Autodesk Fusion 360 part; units mm, degrees
(part 11 of 28)
  line L2789 (27.591, 54.8062) -> (27.7738, 54.7468)
  line L2790 (27.7738, 54.7468) -> (27.9451, 54.6595)
  line L2791 (27.9451, 54.6595) -> (28.1006, 54.5465)
  line L2792 (28.1006, 54.5465) -> (28.2365, 54.4106)
  line L2793 (28.2365, 54.4106) -> (28.3495, 54.2551)
  line L2794 (28.3495, 54.2551) -> (28.3869, 54.1816)
  line L2795 (28.3869, 54.1816) -> (32.118, 57.9127)
  line L2796 (32.118, 57.9127) -> (32.118, 59.7489)
  line L2797 (32.118, 59.7489) -> (32.0649, 59.7759)
  line L2798 (32.0649, 59.7759) -> (31.9062, 59.8912)
  line L2799 (31.9062, 59.8912) -> (31.7675, 60.0299)
  line L2800 (31.7675, 60.0299) -> (31.6522, 60.1886)
  line L2801 (31.6522, 60.1886) -> (31.5632, 60.3634)
  line L2802 (31.5632, 60.3634) -> (31.5026, 60.5499)
  line L2803 (31.5026, 60.5499) -> (31.4719, 60.7437)
  line L2804 (31.4719, 60.7437) -> (31.468, 60.8417)
  line L2805 (31.468, 60.8417) -> (31.468, 61.3417)
  line L2806 (31.468, 61.3417) -> (31.4719, 61.4398)
  line L2807 (31.4719, 61.4398) -> (31.4787, 61.4826)
  line L2808 (31.4787, 61.4826) -> (26.2873, 66.6739)
  line L2809 (26.2873, 66.6739) -> (26.2356, 66.7329)
  line L2810 (26.2356, 66.7329) -> (26.1573, 66.8686)
  line L2811 (26.1573, 66.8686) -> (26.1167, 67.0199)
  line L2812 (26.1167, 67.0199) -> (26.1116, 67.0982)
  line L2813 (26.1116, 67.0982) -> (26.1116, 73.4443)
  line L2814 (26.1116, 73.4443) -> (26.0772, 73.4673)
  line L2815 (26.0772, 73.4673) -> (25.9386, 73.6059)
  line L2816 (25.9386, 73.6059) -> (25.8297, 73.7689)
  line L2817 (25.8297, 73.7689) -> (25.7547, 73.95)
  line L2818 (25.7547, 73.95) -> (25.7164, 74.1423)
  line L2819 (25.7164, 74.1423) -> (25.7116, 74.2403)
  line L2820 (25.7116, 74.2403) -> (25.7116, 75.4403)
  line L2821 (25.7116, 75.4403) -> (25.7164, 75.5383)
  line L2822 (25.7164, 75.5383) -> (25.7547, 75.7306)
  line L2823 (25.7547, 75.7306) -> (25.8297, 75.9117)
  line L2824 (25.8297, 75.9117) -> (25.9386, 76.0747)
  line L2825 (25.9386, 76.0747) -> (26.0772, 76.2133)
  line L2826 (26.0772, 76.2133) -> (26.2402, 76.3222)
  line L2827 (26.2402, 76.3222) -> (26.4213, 76.3972)
  line L2828 (26.4213, 76.3972) -> (26.6136, 76.4355)
  line L2829 (26.6136, 76.4355) -> (26.8096, 76.4355)
  line L2830 (26.8096, 76.4355) -> (27.0019, 76.3972)
  line L2831 (61.9269, 76.3972) -> (62.108, 76.3222)
  line L2832 (62.108, 76.3222) -> (62.271, 76.2133)
  line L2833 (62.271, 76.2133) -> (62.4096, 76.0747)
  line L2834 (62.4096, 76.0747) -> (62.5185, 75.9117)
  line L2835 (62.5185, 75.9117) -> (62.5935, 75.7306)
  line L2836 (62.5935, 75.7306) -> (62.6318, 75.5383)
  line L2837 (62.6318, 75.5383) -> (62.6366, 75.4403)
  line L2838 (62.6366, 75.4403) -> (62.6366, 74.2403)
  line L2839 (62.6366, 74.2403) -> (62.6318, 74.1423)
  line L2840 (62.6318, 74.1423) -> (62.5935, 73.95)
  line L2841 (62.5935, 73.95) -> (62.5185, 73.7689)
  line L2842 (62.5185, 73.7689) -> (62.4096, 73.6059)
  line L2843 (62.4096, 73.6059) -> (62.271, 73.4673)
  line L2844 (62.271, 73.4673) -> (62.2366, 73.4443)
  line L2845 (62.2366, 73.4443) -> (62.2366, 67.3467)
  line L2846 (62.2366, 67.3467) -> (67.113, 62.4703)
  line L2847 (67.113, 62.4703) -> (67.1647, 62.4966)
  line L2848 (67.1647, 62.4966) -> (67.3512, 62.5572)
  line L2849 (67.3512, 62.5572) -> (67.545, 62.5879)
  line L2850 (67.545, 62.5879) -> (67.7411, 62.5879)
  line L2851 (67.7411, 62.5879) -> (67.9348, 62.5572)
  line L2852 (67.9349, 62.5572) -> (68.1214, 62.4966)
  line L2853 (68.1214, 62.4966) -> (68.2962, 62.4075)
  line L2854 (68.2962, 62.4075) -> (68.4549, 62.2922)
  line L2855 (68.4549, 62.2922) -> (68.5935, 62.1536)
  line L2856 (68.5935, 62.1536) -> (68.7088, 61.9949)
  line L2857 (68.7088, 61.9949) -> (68.7979, 61.8201)
  line L2858 (68.7979, 61.8201) -> (68.8585, 61.6335)
  line L2859 (68.8585, 61.6335) -> (68.8892, 61.4398)
  line L2860 (68.8892, 61.4398) -> (68.893, 61.3417)
  line L2861 (68.893, 61.3417) -> (68.893, 60.8417)
  line L2862 (68.893, 60.8417) -> (68.8892, 60.7437)
  line L2863 (68.8892, 60.7437) -> (68.8585, 60.5499)
  line L2864 (68.8585, 60.5499) -> (68.7979, 60.3634)
  line L2865 (68.7979, 60.3634) -> (68.7088, 60.1886)
  line L2866 (68.7088, 60.1886) -> (68.5935, 60.0299)
  line L2867 (68.5935, 60.0299) -> (68.4549, 59.8912)
  line L2868 (68.4549, 59.8912) -> (68.2962, 59.7759)
  line L2869 (68.2962, 59.7759) -> (68.243, 59.7489)
  line L2870 (68.243, 59.7489) -> (68.243, 57.9582)
  line L2871 (68.243, 57.9582) -> (68.2499, 57.9463)
  line L2872 (68.2499, 57.9463) -> (68.2904, 57.795)
  line L2873 (68.2904, 57.795) -> (68.2904, 57.6384)
  line L2874 (68.2904, 57.6384) -> (68.2499, 57.4871)
  line L2875 (68.2499, 57.4871) -> (68.1716, 57.3515)
  line L2876 (68.1716, 57.3515) -> (68.1716, 57.3515)
  line L2877 (68.1716, 57.3515) -> (68.1198, 57.2925)
  line L2878 (68.1198, 57.2925) -> (63.7431, 52.9157)
  line L2879 (63.7431, 52.9157) -> (63.6841, 52.864)
  line L2880 (63.6841, 52.864) -> (63.5485, 52.7857)
  line L2881 (63.5485, 52.7857) -> (63.4114, 52.7489)
  line L2882 (63.4114, 52.7489) -> (63.3618, 52.5962)
  line L2883 (63.3618, 52.5962) -> (63.2745, 52.4249)
  line L2884 (63.2745, 52.4249) -> (63.1615, 52.2694)
  line L2885 (63.1615, 52.2694) -> (63.0256, 52.1335)
  line L2886 (63.0256, 52.1335) -> (62.8701, 52.0205)
  line L2887 (62.8701, 52.0205) -> (62.6988, 51.9332)
  line L2888 (62.6988, 51.9332) -> (62.516, 51.8738)
  line L2889 (62.516, 51.8738) -> (62.3261, 51.8438)
  line L2890 (62.3261, 51.8438) -> (62.1339, 51.8438)
  line L2891 (62.1339, 51.8438) -> (61.944, 51.8738)
  line L2892 (61.944, 51.8738) -> (61.7612, 51.9332)
  line L2893 (61.7612, 51.9332) -> (61.5899, 52.0205)
  line L2894 (61.5899, 52.0205) -> (61.4344, 52.1335)
  line L2895 (61.4344, 52.1335) -> (61.2985, 52.2694)
  line L2896 (61.2985, 52.2694) -> (61.1855, 52.4249)
  line L2897 (61.1855, 52.4249) -> (61.0982, 52.5962)
  line L2898 (61.0982, 52.5962) -> (61.0388, 52.779)
  line L2899 (61.0388, 52.779) -> (61.0088, 52.9689)
  line L2900 (61.0088, 52.9689) -> (61.005, 53.065)
  line L2901 (61.005, 53.065) -> (61.005, 53.615)
  line L2902 (61.005, 53.615) -> (61.0088, 53.7111)
  line L2903 (61.0088, 53.7111) -> (61.0388, 53.901)
  line L2904 (61.0388, 53.901) -> (61.0982, 54.0838)
  line L2905 (61.0982, 54.0838) -> (61.1855, 54.2551)
  line L2906 (61.1855, 54.2551) -> (61.2985, 54.4106)
  line L2907 (61.2985, 54.4106) -> (61.4344, 54.5465)
  line L2908 (61.4344, 54.5465) -> (61.5899, 54.6595)
  line L2909 (61.5899, 54.6595) -> (61.7612, 54.7468)
  line L2910 (61.7612, 54.7468) -> (61.944, 54.8062)
  line L2911 (61.944, 54.8062) -> (62.1339, 54.8362)
  line L2912 (62.1339, 54.8362) -> (62.3261, 54.8362)
  line L2913 (62.3261, 54.8362) -> (62.516, 54.8062)
  line L2914 (62.516, 54.8062) -> (62.6988, 54.7468)
  line L2915 (62.6988, 54.7468) -> (62.8701, 54.6595)
  line L2916 (62.8701, 54.6595) -> (63.0256, 54.5465)
  line L2917 (63.0256, 54.5465) -> (63.1615, 54.4106)
  line L2918 (63.1615, 54.4106) -> (63.2745, 54.2551)
  line L2919 (63.2745, 54.2551) -> (63.3119, 54.1816)
  line L2920 (63.3119, 54.1816) -> (67.043, 57.9127)
  line L2921 (67.043, 57.9127) -> (67.043, 59.7489)
  line L2922 (67.043, 59.7489) -> (66.9899, 59.7759)
  line L2923 (66.9899, 59.7759) -> (66.8312, 59.8912)
  line L2924 (66.8312, 59.8912) -> (66.6925, 60.0299)
  line L2925 (66.6925, 60.0299) -> (66.5772, 60.1886)
  line L2926 (66.5772, 60.1886) -> (66.4882, 60.3634)
  line L2927 (66.4882, 60.3634) -> (66.4276, 60.5499)
  line L2928 (66.4276, 60.5499) -> (66.3969, 60.7437)
  line L2929 (66.3969, 60.7437) -> (66.393, 60.8417)
  line L2930 (66.393, 60.8417) -> (66.393, 61.3417)
  line L2931 (66.393, 61.3417) -> (66.3969, 61.4398)
  line L2932 (66.3969, 61.4398) -> (66.4037, 61.4826)
  line L2933 (66.4037, 61.4826) -> (61.2123, 66.6739)
  line L2934 (61.2123, 66.6739) -> (61.1606, 66.7329)
  line L2935 (61.1606, 66.7329) -> (61.0823, 66.8686)
  line L2936 (61.0823, 66.8686) -> (61.0417, 67.0199)
  line L2937 (61.0417, 67.0199) -> (61.0366, 67.0982)
  line L2938 (61.0366, 67.0982) -> (61.0366, 73.4443)
  line L2939 (61.0366, 73.4443) -> (61.0022, 73.4673)
  line L2940 (61.0022, 73.4673) -> (60.8636, 73.6059)
  line L2941 (60.8636, 73.6059) -> (60.7547, 73.7689)
  line L2942 (60.7547, 73.7689) -> (60.6797, 73.95)
  line L2943 (60.6797, 73.95) -> (60.6414, 74.1423)
  line L2944 (60.6414, 74.1423) -> (60.6366, 74.2403)
  line L2945 (60.6366, 74.2403) -> (60.6366, 75.4403)
  line L2946 (60.6366, 75.4403) -> (60.6414, 75.5383)
  line L2947 (60.6414, 75.5383) -> (60.6797, 75.7306)
  line L2948 (60.6797, 75.7306) -> (60.7547, 75.9117)
  line L2949 (60.7547, 75.9117) -> (60.8636, 76.0747)
  line L2950 (60.8636, 76.0747) -> (61.0022, 76.2133)
  line L2951 (61.0022, 76.2133) -> (61.1652, 76.3222)
  line L2952 (61.1652, 76.3222) -> (61.3463, 76.3972)
  line L2953 (61.3463, 76.3972) -> (61.5386, 76.4355)
  line L2954 (61.5386, 76.4355) -> (61.7346, 76.4355)
  line L2955 (61.7346, 76.4355) -> (61.9269, 76.3972)
  line L2956 (96.8519, 76.3972) -> (97.033, 76.3222)
  line L2957 (97.033, 76.3222) -> (97.196, 76.2133)
  line L2958 (97.196, 76.2133) -> (97.3346, 76.0747)
  line L2959 (97.3346, 76.0747) -> (97.4435, 75.9117)
  line L2960 (97.4435, 75.9117) -> (97.5185, 75.7306)
  line L2961 (97.5185, 75.7306) -> (97.5568, 75.5383)
  line L2962 (97.5568, 75.5383) -> (97.5616, 75.4403)
  line L2963 (97.5616, 75.4403) -> (97.5616, 74.2403)
  line L2964 (97.5616, 74.2403) -> (97.5568, 74.1423)
  line L2965 (97.5568, 74.1423) -> (97.5185, 73.95)
  line L2966 (97.5185, 73.95) -> (97.4435, 73.7689)
  line L2967 (97.4435, 73.7689) -> (97.3346, 73.6059)
  line L2968 (97.3346, 73.6059) -> (97.196, 73.4673)
  line L2969 (97.196, 73.4673) -> (97.1616, 73.4443)
  line L2970 (97.1616, 73.4443) -> (97.1616, 67.3467)
  line L2971 (97.1616, 67.3467) -> (102.038, 62.4703)
  line L2972 (102.038, 62.4703) -> (102.0897, 62.4966)
  line L2973 (102.0897, 62.4966) -> (102.2762, 62.5572)
  line L2974 (102.2762, 62.5572) -> (102.47, 62.5879)
  line L2975 (102.47, 62.5879) -> (102.6661, 62.5879)
  line L2976 (102.6661, 62.5879) -> (102.8598, 62.5572)
  line L2977 (102.8598, 62.5572) -> (103.0464, 62.4966)
  line L2978 (103.0464, 62.4966) -> (103.2212, 62.4075)
  line L2979 (103.2212, 62.4075) -> (103.3799, 62.2922)
  line L2980 (103.3799, 62.2922) -> (103.5186, 62.1536)
  line L2981 (103.5186, 62.1536) -> (103.6338, 61.9949)
  line L2982 (103.6338, 61.9949) -> (103.7229, 61.8201)
  line L2983 (103.7229, 61.8201) -> (103.7835, 61.6335)
  line L2984 (103.7835, 61.6335) -> (103.8142, 61.4398)
  line L2985 (103.8142, 61.4398) -> (103.818, 61.3417)
  line L2986 (103.818, 61.3417) -> (103.818, 60.8417)
  line L2987 (103.818, 60.8417) -> (103.8142, 60.7437)
  line L2988 (103.8142, 60.7437) -> (103.7835, 60.5499)
  line L2989 (103.7835, 60.5499) -> (103.7229, 60.3634)
  line L2990 (103.7229, 60.3634) -> (103.6338, 60.1886)
  line L2991 (103.6338, 60.1886) -> (103.5186, 60.0299)
  line L2992 (103.5186, 60.0299) -> (103.3799, 59.8912)
  line L2993 (103.3799, 59.8912) -> (103.2212, 59.7759)
  line L2994 (103.2212, 59.7759) -> (103.168, 59.7489)
  line L2995 (103.168, 59.7489) -> (103.168, 57.9582)
  line L2996 (103.168, 57.9582) -> (103.1749, 57.9463)
  line L2997 (103.1749, 57.9463) -> (103.2154, 57.795)
  line L2998 (103.2154, 57.795) -> (103.2154, 57.6384)
  line L2999 (103.2154, 57.6384) -> (103.1749, 57.4871)
  line L3000 (103.1749, 57.4871) -> (103.0966, 57.3515)
  line L3001 (103.0966, 57.3515) -> (103.0966, 57.3515)
  line L3002 (103.0966, 57.3515) -> (103.0448, 57.2925)
  line L3003 (103.0448, 57.2925) -> (98.6681, 52.9157)
  line L3004 (98.6681, 52.9157) -> (98.6091, 52.864)
  line L3005 (98.6091, 52.864) -> (98.4735, 52.7857)
  line L3006 (98.4735, 52.7857) -> (98.3364, 52.7489)
  line L3007 (98.3364, 52.7489) -> (98.2868, 52.5962)
  line L3008 (98.2868, 52.5962) -> (98.1995, 52.4249)
  line L3009 (98.1995, 52.4249) -> (98.0865, 52.2694)
  line L3010 (98.0865, 52.2694) -> (97.9506, 52.1335)
  line L3011 (97.9506, 52.1335) -> (97.7951, 52.0205)
  line L3012 (97.7951, 52.0205) -> (97.6238, 51.9332)
  line L3013 (97.6238, 51.9332) -> (97.441, 51.8738)
  line L3014 (97.441, 51.8738) -> (97.2511, 51.8438)
  line L3015 (97.2511, 51.8438) -> (97.0589, 51.8438)
  line L3016 (97.0589, 51.8438) -> (96.869, 51.8738)
  line L3017 (96.869, 51.8738) -> (96.6862, 51.9332)
  line L3018 (96.6862, 51.9332) -> (96.5149, 52.0205)
  line L3019 (96.5149, 52.0205) -> (96.3594, 52.1335)
  line L3020 (96.3594, 52.1335) -> (96.2235, 52.2694)
  line L3021 (96.2235, 52.2694) -> (96.1105, 52.4249)
  line L3022 (96.1105, 52.4249) -> (96.0232, 52.5962)
  line L3023 (96.0232, 52.5962) -> (95.9638, 52.779)
  line L3024 (95.9638, 52.779) -> (95.9338, 52.9689)
  line L3025 (95.9338, 52.9689) -> (95.93, 53.065)
  line L3026 (95.93, 53.065) -> (95.93, 53.615)
  line L3027 (95.93, 53.615) -> (95.9338, 53.7111)
  line L3028 (95.9338, 53.7111) -> (95.9638, 53.901)
  line L3029 (95.9638, 53.901) -> (96.0232, 54.0838)
  line L3030 (96.0232, 54.0838) -> (96.1105, 54.2551)
  line L3031 (96.1105, 54.2551) -> (96.2235, 54.4106)
  line L3032 (96.2235, 54.4106) -> (96.3594, 54.5465)
  line L3033 (96.3594, 54.5465) -> (96.5149, 54.6595)
  line L3034 (96.5149, 54.6595) -> (96.6862, 54.7468)
  line L3035 (96.6862, 54.7468) -> (96.869, 54.8062)
  line L3036 (96.869, 54.8062) -> (97.0589, 54.8362)
  line L3037 (97.0589, 54.8362) -> (97.2511, 54.8362)
  line L3038 (97.2511, 54.8362) -> (97.441, 54.8062)
  line L3039 (97.441, 54.8062) -> (97.6238, 54.7468)
  line L3040 (97.6238, 54.7468) -> (97.7951, 54.6595)
  line L3041 (97.7951, 54.6595) -> (97.9506, 54.5465)
  line L3042 (97.9506, 54.5465) -> (98.0865, 54.4106)
  line L3043 (98.0865, 54.4106) -> (98.1995, 54.2551)
  line L3044 (98.1995, 54.2551) -> (98.2369, 54.1816)
  line L3045 (98.2369, 54.1816) -> (101.968, 57.9127)
  line L3046 (101.968, 57.9127) -> (101.968, 59.7489)
  line L3047 (101.968, 59.7489) -> (101.9149, 59.7759)
  line L3048 (101.9149, 59.7759) -> (101.7562, 59.8912)
  line L3049 (101.7562, 59.8912) -> (101.6175, 60.0299)
  line L3050 (101.6175, 60.0299) -> (101.5022, 60.1886)
  line L3051 (101.5022, 60.1886) -> (101.4132, 60.3634)
  line L3052 (101.4132, 60.3634) -> (101.3526, 60.5499)
  line L3053 (101.3526, 60.5499) -> (101.3219, 60.7437)
  line L3054 (101.3219, 60.7437) -> (101.318, 60.8417)
  line L3055 (101.318, 60.8417) -> (101.318, 61.3417)
  line L3056 (101.318, 61.3417) -> (101.3219, 61.4398)
  line L3057 (101.3219, 61.4398) -> (101.3287, 61.4826)
  line L3058 (101.3287, 61.4826) -> (96.1373, 66.6739)
  line L3059 (96.1373, 66.6739) -> (96.0856, 66.7329)
  line L3060 (96.0856, 66.7329) -> (96.0073, 66.8686)
  line L3061 (96.0073, 66.8686) -> (95.9667, 67.0199)
  line L3062 (95.9667, 67.0199) -> (95.9616, 67.0982)
  line L3063 (95.9616, 67.0982) -> (95.9616, 73.4443)
  line L3064 (95.9616, 73.4443) -> (95.9272, 73.4673)
  line L3065 (95.9272, 73.4673) -> (95.7886, 73.6059)
  line L3066 (95.7886, 73.6059) -> (95.6797, 73.7689)
  line L3067 (95.6797, 73.7689) -> (95.6047, 73.95)
  line L3068 (95.6047, 73.95) -> (95.5664, 74.1423)
  line L3069 (95.5664, 74.1423) -> (95.5616, 74.2403)
  line L3070 (95.5616, 74.2403) -> (95.5616, 75.4403)
  line L3071 (95.5616, 75.4403) -> (95.5664, 75.5383)
  line L3072 (95.5664, 75.5383) -> (95.6047, 75.7306)
  line L3073 (95.6047, 75.7306) -> (95.6797, 75.9117)
  line L3074 (95.6797, 75.9117) -> (95.7886, 76.0747)
  line L3075 (95.7886, 76.0747) -> (95.9272, 76.2133)
  line L3076 (95.9272, 76.2133) -> (96.0902, 76.3222)
  line L3077 (96.0902, 76.3222) -> (96.2713, 76.3972)
  line L3078 (96.2713, 76.3972) -> (96.4636, 76.4355)
  line L3079 (96.4636, 76.4355) -> (96.6596, 76.4355)
  line L3080 (96.6596, 76.4355) -> (96.8519, 76.3972)
  line L3081 (131.7769, 76.3972) -> (131.958, 76.3222)
  line L3082 (131.958, 76.3222) -> (132.121, 76.2133)
  line L3083 (132.121, 76.2133) -> (132.2596, 76.0747)
  line L3084 (132.2596, 76.0747) -> (132.3685, 75.9117)
  line L3085 (132.3685, 75.9117) -> (132.4435, 75.7306)
  line L3086 (132.4435, 75.7306) -> (132.4818, 75.5383)
  line L3087 (132.4818, 75.5383) -> (132.4866, 75.4403)
  line L3088 (132.4866, 75.4403) -> (132.4866, 74.2403)
  line L3089 (132.4866, 74.2403) -> (132.4818, 74.1423)
  line L3090 (132.4818, 74.1423) -> (132.4435, 73.95)
  line L3091 (132.4435, 73.95) -> (132.3685, 73.7689)
  line L3092 (132.3685, 73.7689) -> (132.2596, 73.6059)
  line L3093 (132.2596, 73.6059) -> (132.121, 73.4673)
  line L3094 (132.121, 73.4673) -> (132.0866, 73.4443)
  line L3095 (132.0866, 73.4443) -> (132.0866, 67.3467)
  line L3096 (132.0866, 67.3467) -> (136.963, 62.4703)
  line L3097 (136.963, 62.4703) -> (137.0147, 62.4966)
  line L3098 (137.0147, 62.4966) -> (137.2012, 62.5572)
  line L3099 (137.2012, 62.5572) -> (137.395, 62.5879)
  line L3100 (137.395, 62.5879) -> (137.5911, 62.5879)
  line L3101 (137.5911, 62.5879) -> (137.7849, 62.5572)
  line L3102 (137.7849, 62.5572) -> (137.9714, 62.4966)
  line L3103 (137.9714, 62.4966) -> (138.1462, 62.4075)
  line L3104 (138.1462, 62.4075) -> (138.3049, 62.2922)
  line L3105 (138.3049, 62.2922) -> (138.4436, 62.1536)
  line L3106 (138.4436, 62.1536) -> (138.5588, 61.9949)
  line L3107 (138.5588, 61.9949) -> (138.6479, 61.8201)
  line L3108 (138.6479, 61.8201) -> (138.7085, 61.6335)
  line L3109 (138.7085, 61.6335) -> (138.7392, 61.4398)
  line L3110 (138.7392, 61.4398) -> (138.743, 61.3417)
  line L3111 (138.743, 61.3417) -> (138.743, 60.8417)
  line L3112 (138.743, 60.8417) -> (138.7392, 60.7437)
  line L3113 (138.7392, 60.7437) -> (138.7085, 60.5499)
  line L3114 (138.7085, 60.5499) -> (138.6479, 60.3634)
  line L3115 (138.6479, 60.3634) -> (138.5588, 60.1886)
  line L3116 (138.5588, 60.1886) -> (138.4436, 60.0299)
  line L3117 (138.4436, 60.0299) -> (138.3049, 59.8912)
  line L3118 (138.3049, 59.8912) -> (138.1462, 59.7759)
  line L3119 (138.1462, 59.7759) -> (138.093, 59.7489)
  line L3120 (138.093, 59.7489) -> (138.093, 57.9582)
  line L3121 (138.093, 57.9582) -> (138.0999, 57.9463)
  line L3122 (138.0999, 57.9463) -> (138.1404, 57.795)
  line L3123 (138.1404, 57.795) -> (138.1404, 57.6384)
  line L3124 (138.1404, 57.6384) -> (138.0999, 57.4871)
  line L3125 (138.0999, 57.4871) -> (138.0216, 57.3515)
  line L3126 (138.0216, 57.3515) -> (138.0216, 57.3515)
  line L3127 (138.0216, 57.3515) -> (137.9698, 57.2925)
  line L3128 (137.9698, 57.2925) -> (133.5931, 52.9157)
  line L3129 (133.5931, 52.9157) -> (133.5341, 52.864)
  line L3130 (133.5341, 52.864) -> (133.3985, 52.7857)
  line L3131 (133.3985, 52.7857) -> (133.2614, 52.7489)
  line L3132 (133.2614, 52.7489) -> (133.2118, 52.5962)
  line L3133 (133.2118, 52.5962) -> (133.1245, 52.4249)
  line L3134 (133.1245, 52.4249) -> (133.0115, 52.2694)
  line L3135 (133.0115, 52.2694) -> (132.8756, 52.1335)
  line L3136 (132.8756, 52.1335) -> (132.7201, 52.0205)
  line L3137 (132.7201, 52.0205) -> (132.5488, 51.9332)
  line L3138 (132.5488, 51.9332) -> (132.366, 51.8738)
  line L3139 (132.366, 51.8738) -> (132.1761, 51.8438)
  line L3140 (132.1761, 51.8438) -> (131.9839, 51.8438)
  line L3141 (131.9839, 51.8438) -> (131.794, 51.8738)
  line L3142 (131.794, 51.8738) -> (131.6112, 51.9332)
  line L3143 (131.6112, 51.9332) -> (131.4399, 52.0205)
  line L3144 (131.4399, 52.0205) -> (131.2844, 52.1335)
  line L3145 (131.2844, 52.1335) -> (131.1485, 52.2694)
  line L3146 (131.1485, 52.2694) -> (131.0355, 52.4249)
  line L3147 (131.0355, 52.4249) -> (130.9482, 52.5962)
  line L3148 (130.9482, 52.5962) -> (130.8888, 52.779)
  line L3149 (130.8888, 52.779) -> (130.8588, 52.9689)
  line L3150 (130.8588, 52.9689) -> (130.855, 53.065)
  line L3151 (130.855, 53.065) -> (130.855, 53.615)
  line L3152 (130.855, 53.615) -> (130.8588, 53.7111)
  line L3153 (130.8588, 53.7111) -> (130.8888, 53.901)
  line L3154 (130.8888, 53.901) -> (130.9482, 54.0838)
  line L3155 (130.9482, 54.0838) -> (131.0355, 54.2551)
  line L3156 (131.0355, 54.2551) -> (131.1485, 54.4106)
  line L3157 (131.1485, 54.4106) -> (131.2844, 54.5465)
  line L3158 (131.2844, 54.5465) -> (131.4399, 54.6595)
  line L3159 (131.4399, 54.6595) -> (131.6112, 54.7468)
  line L3160 (131.6112, 54.7468) -> (131.794, 54.8062)
  line L3161 (131.794, 54.8062) -> (131.9839, 54.8362)
  line L3162 (131.9839, 54.8362) -> (132.1761, 54.8362)
  line L3163 (132.1761, 54.8362) -> (132.366, 54.8062)
  line L3164 (132.366, 54.8062) -> (132.5488, 54.7468)
  line L3165 (132.5488, 54.7468) -> (132.7201, 54.6595)
  line L3166 (132.7201, 54.6595) -> (132.8756, 54.5465)
  line L3167 (132.8756, 54.5465) -> (133.0115, 54.4106)
  line L3168 (133.0115, 54.4106) -> (133.1245, 54.2551)
  line L3169 (133.1245, 54.2551) -> (133.1619, 54.1816)
  line L3170 (133.1619, 54.1816) -> (136.893, 57.9127)
  line L3171 (136.893, 57.9127) -> (136.893, 59.7489)
  line L3172 (136.893, 59.7489) -> (136.8399, 59.7759)
  line L3173 (136.8399, 59.7759) -> (136.6812, 59.8912)
  line L3174 (136.6812, 59.8912) -> (136.5425, 60.0299)
  line L3175 (136.5425, 60.0299) -> (136.4272, 60.1886)
  line L3176 (136.4272, 60.1886) -> (136.3382, 60.3634)
  line L3177 (136.3382, 60.3634) -> (136.2776, 60.5499)
  line L3178 (136.2776, 60.5499) -> (136.2469, 60.7437)
  line L3179 (136.2469, 60.7437) -> (136.243, 60.8417)
  line L3180 (136.243, 60.8417) -> (136.243, 61.3417)
  line L3181 (136.243, 61.3417) -> (136.2469, 61.4398)
  line L3182 (136.2469, 61.4398) -> (136.2537, 61.4826)
  line L3183 (136.2537, 61.4826) -> (131.0623, 66.6739)
  line L3184 (131.0623, 66.6739) -> (131.0106, 66.7329)
  line L3185 (131.0106, 66.7329) -> (130.9323, 66.8686)
  line L3186 (130.9323, 66.8686) -> (130.8917, 67.0199)
  line L3187 (130.8917, 67.0199) -> (130.8866, 67.0982)
  line L3188 (130.8866, 67.0982) -> (130.8866, 73.4443)
  line L3189 (130.8866, 73.4443) -> (130.8522, 73.4673)
  line L3190 (130.8522, 73.4673) -> (130.7136, 73.6059)
  line L3191 (130.7136, 73.6059) -> (130.6047, 73.7689)
  line L3192 (130.6047, 73.7689) -> (130.5297, 73.95)
  line L3193 (130.5297, 73.95) -> (130.4914, 74.1423)
  line L3194 (130.4914, 74.1423) -> (130.4866, 74.2403)
  line L3195 (130.4866, 74.2403) -> (130.4866, 75.4403)
  line L3196 (130.4866, 75.4403) -> (130.4914, 75.5383)
  line L3197 (130.4914, 75.5383) -> (130.5297, 75.7306)
  line L3198 (130.5297, 75.7306) -> (130.6047, 75.9117)
  line L3199 (130.6047, 75.9117) -> (130.7136, 76.0747)
  line L3200 (130.7136, 76.0747) -> (130.8522, 76.2133)
  line L3201 (130.8522, 76.2133) -> (131.0152, 76.3222)
  line L3202 (131.0152, 76.3222) -> (131.1963, 76.3972)
  line L3203 (131.1963, 76.3972) -> (131.3886, 76.4355)
  line L3204 (131.3886, 76.4355) -> (131.5846, 76.4355)
  line L3205 (131.5846, 76.4355) -> (131.7769, 76.3972)
  line L3206 (16.4157, 55.2193) -> (16.5985, 55.1599)
  line L3207 (16.5985, 55.1599) -> (16.7697, 55.0726)
  line L3208 (16.7697, 55.0726) -> (16.9253, 54.9596)
  line L3209 (16.9253, 54.9596) -> (17.0612, 54.8237)
  line L3210 (17.0612, 54.8237) -> (17.1742, 54.6682)
  line L3211 (17.1742, 54.6682) -> (17.2614, 54.4969)
  line L3212 (17.2614, 54.4969) -> (17.3208, 54.3141)
  line L3213 (17.3208, 54.3141) -> (17.3509, 54.1242)
  line L3214 (17.3509, 54.1242) -> (17.3547, 54.0281)
  line L3215 (17.3547, 54.0281) -> (17.3547, 53.4781)
  line L3216 (17.3547, 53.4781) -> (17.3509, 53.382)
  line L3217 (17.3509, 53.382) -> (17.3208, 53.1921)
  line L3218 (17.3208, 53.1921) -> (17.2614, 53.0093)
  line L3219 (17.2614, 53.0093) -> (17.1742, 52.8381)
  line L3220 (17.1742, 52.8381) -> (17.0612, 52.6825)
  line L3221 (17.0612, 52.6825) -> (16.9253, 52.5466)
  line L3222 (16.9253, 52.5466) -> (16.7697, 52.4336)
  line L3223 (16.7697, 52.4336) -> (16.5985, 52.3464)
  line L3224 (16.5985, 52.3464) -> (16.4157, 52.287)
  line L3225 (16.4157, 52.287) -> (16.2258, 52.2569)
  line L3226 (16.2258, 52.2569) -> (16.0336, 52.2569)
  line L3227 (16.0336, 52.2569) -> (15.8437, 52.287)
  line L3228 (15.8437, 52.287) -> (15.6609, 52.3464)
  line L3229 (15.6609, 52.3464) -> (15.4896, 52.4336)
  line L3230 (15.4896, 52.4336) -> (15.3341, 52.5466)
  line L3231 (15.3341, 52.5466) -> (15.1982, 52.6825)
  line L3232 (15.1982, 52.6825) -> (15.0852, 52.8381)
  line L3233 (15.0852, 52.8381) -> (14.9979, 53.0093)
  line L3234 (14.9979, 53.0093) -> (14.9385, 53.1921)
  line L3235 (14.9385, 53.1921) -> (14.9085, 53.382)
  line L3236 (14.9085, 53.382) -> (14.9047, 53.4781)
  line L3237 (14.9047, 53.4781) -> (14.9047, 54.0281)
  line L3238 (14.9047, 54.0281) -> (14.9085, 54.1242)
  line L3239 (14.9085, 54.1242) -> (14.9385, 54.3141)
  line L3240 (14.9385, 54.3141) -> (14.9979, 54.4969)
  line L3241 (14.9979, 54.4969) -> (15.0852, 54.6682)
  line L3242 (15.0852, 54.6682) -> (15.1982, 54.8237)
  line L3243 (15.1982, 54.8237) -> (15.3341, 54.9596)
  line L3244 (15.3341, 54.9596) -> (15.4896, 55.0726)
  line L3245 (15.4896, 55.0726) -> (15.6609, 55.1599)
  line L3246 (15.6609, 55.1599) -> (15.8437, 55.2193)
  line L3247 (15.8437, 55.2193) -> (16.0336, 55.2493)
  line L3248 (16.0336, 55.2493) -> (16.2258, 55.2493)
  line L3249 (16.2258, 55.2493) -> (16.4157, 55.2193)
  line L3250 (51.3407, 55.2193) -> (51.5235, 55.1599)
  line L3251 (51.5235, 55.1599) -> (51.6947, 55.0726)
  line L3252 (51.6947, 55.0726) -> (51.8503, 54.9596)
  line L3253 (51.8503, 54.9596) -> (51.9862, 54.8237)
  line L3254 (51.9862, 54.8237) -> (52.0992, 54.6682)
  line L3255 (52.0992, 54.6682) -> (52.1864, 54.4969)
  line L3256 (52.1864, 54.4969) -> (52.2458, 54.3141)
  line L3257 (52.2458, 54.3141) -> (52.2759, 54.1242)
  line L3258 (52.2759, 54.1242) -> (52.2797, 54.0281)
  line L3259 (52.2797, 54.0281) -> (52.2797, 53.4781)
  line L3260 (52.2797, 53.4781) -> (52.2759, 53.382)
  line L3261 (52.2759, 53.382) -> (52.2458, 53.1921)
  line L3262 (52.2458, 53.1921) -> (52.1864, 53.0093)
  line L3263 (52.1864, 53.0093) -> (52.0992, 52.8381)
  line L3264 (52.0992, 52.8381) -> (51.9862, 52.6825)
  line L3265 (51.9862, 52.6825) -> (51.8503, 52.5466)
  line L3266 (51.8503, 52.5466) -> (51.6947, 52.4336)
  line L3267 (51.6947, 52.4336) -> (51.5235, 52.3464)
  line L3268 (51.5235, 52.3464) -> (51.3407, 52.287)
  line L3269 (51.3407, 52.287) -> (51.1508, 52.2569)
  line L3270 (51.1508, 52.2569) -> (50.9586, 52.2569)
  line L3271 (50.9586, 52.2569) -> (50.7687, 52.287)
  line L3272 (50.7687, 52.287) -> (50.5859, 52.3464)
  line L3273 (50.5859, 52.3464) -> (50.4146, 52.4336)
  line L3274 (50.4146, 52.4336) -> (50.2591, 52.5466)
  line L3275 (50.2591, 52.5466) -> (50.1232, 52.6825)
  line L3276 (50.1232, 52.6825) -> (50.0102, 52.8381)
  line L3277 (50.0102, 52.8381) -> (49.9229, 53.0093)
  line L3278 (49.9229, 53.0093) -> (49.8635, 53.1921)
  line L3279 (49.8635, 53.1921) -> (49.8335, 53.382)
  line L3280 (49.8335, 53.382) -> (49.8297, 53.4781)
  line L3281 (49.8297, 53.4781) -> (49.8297, 54.0281)
  line L3282 (49.8297, 54.0281) -> (49.8335, 54.1242)
  line L3283 (49.8335, 54.1242) -> (49.8635, 54.3141)
  line L3284 (49.8635, 54.3141) -> (49.9229, 54.4969)
  line L3285 (49.9229, 54.4969) -> (50.0102, 54.6682)
  line L3286 (50.0102, 54.6682) -> (50.1232, 54.8237)
  line L3287 (50.1232, 54.8237) -> (50.2591, 54.9596)
  line L3288 (50.2591, 54.9596) -> (50.4146, 55.0726)
  line L3289 (50.4146, 55.0726) -> (50.5859, 55.1599)
  line L3290 (50.5859, 55.1599) -> (50.7687, 55.2193)
  line L3291 (50.7687, 55.2193) -> (50.9586, 55.2493)
  line L3292 (50.9586, 55.2493) -> (51.1508, 55.2493)
  line L3293 (51.1508, 55.2493) -> (51.3407, 55.2193)
  line L3294 (86.2657, 55.2193) -> (86.4485, 55.1599)
  line L3295 (86.4485, 55.1599) -> (86.6197, 55.0726)
  line L3296 (86.6197, 55.0726) -> (86.7753, 54.9596)
  line L3297 (86.7753, 54.9596) -> (86.9112, 54.8237)
  line L3298 (86.9112, 54.8237) -> (87.0242, 54.6682)
  line L3299 (87.0242, 54.6682) -> (87.1114, 54.4969)
  line L3300 (87.1114, 54.4969) -> (87.1708, 54.3141)
  line L3301 (87.1708, 54.3141) -> (87.2009, 54.1242)
  line L3302 (87.2009, 54.1242) -> (87.2047, 54.0281)
  line L3303 (87.2047, 54.0281) -> (87.2047, 53.4781)
  line L3304 (87.2047, 53.4781) -> (87.2009, 53.382)
  line L3305 (87.2009, 53.382) -> (87.1708, 53.1921)
  line L3306 (87.1708, 53.1921) -> (87.1114, 53.0093)
  line L3307 (87.1114, 53.0093) -> (87.0242, 52.8381)
  line L3308 (87.0242, 52.8381) -> (86.9112, 52.6825)
  line L3309 (86.9112, 52.6825) -> (86.7753, 52.5466)
  line L3310 (86.7753, 52.5466) -> (86.6197, 52.4336)
  line L3311 (86.6197, 52.4336) -> (86.4485, 52.3464)
  line L3312 (86.4485, 52.3464) -> (86.2657, 52.287)
  line L3313 (86.2657, 52.287) -> (86.0758, 52.2569)
  line L3314 (86.0758, 52.2569) -> (85.8836, 52.2569)
  line L3315 (85.8836, 52.2569) -> (85.6937, 52.287)
  line L3316 (85.6937, 52.287) -> (85.5109, 52.3464)
  line L3317 (85.5109, 52.3464) -> (85.3396, 52.4336)
  line L3318 (85.3396, 52.4336) -> (85.1841, 52.5466)
  line L3319 (85.1841, 52.5466) -> (85.0482, 52.6825)
  line L3320 (85.0482, 52.6825) -> (84.9352, 52.8381)
  line L3321 (84.9352, 52.8381) -> (84.8479, 53.0093)
  line L3322 (84.8479, 53.0093) -> (84.7885, 53.1921)
  line L3323 (84.7885, 53.1921) -> (84.7585, 53.382)
  line L3324 (84.7585, 53.382) -> (84.7547, 53.4781)
  line L3325 (84.7547, 53.4781) -> (84.7547, 54.0281)
  line L3326 (84.7547, 54.0281) -> (84.7585, 54.1242)
  line L3327 (84.7585, 54.1242) -> (84.7885, 54.3141)
  line L3328 (84.7885, 54.3141) -> (84.8479, 54.4969)
  line L3329 (84.8479, 54.4969) -> (84.9352, 54.6682)
  line L3330 (84.9352, 54.6682) -> (85.0482, 54.8237)
  line L3331 (85.0482, 54.8237) -> (85.1841, 54.9596)
  line L3332 (85.1841, 54.9596) -> (85.3396, 55.0726)
  line L3333 (85.3396, 55.0726) -> (85.5109, 55.1599)
  line L3334 (85.5109, 55.1599) -> (85.6937, 55.2193)
  line L3335 (85.6937, 55.2193) -> (85.8836, 55.2493)
  line L3336 (85.8836, 55.2493) -> (86.0758, 55.2493)
  line L3337 (86.0758, 55.2493) -> (86.2657, 55.2193)
  line L3338 (121.1907, 55.2193) -> (121.3735, 55.1599)
  line L3339 (121.3735, 55.1599) -> (121.5447, 55.0726)
  line L3340 (121.5447, 55.0726) -> (121.7003, 54.9596)
  line L3341 (121.7003, 54.9596) -> (121.8362, 54.8237)
  line L3342 (121.8362, 54.8237) -> (121.9492, 54.6682)
  line L3343 (121.9492, 54.6682) -> (122.0364, 54.4969)
  line L3344 (122.0364, 54.4969) -> (122.0958, 54.3141)
  line L3345 (122.0958, 54.3141) -> (122.1259, 54.1242)
  line L3346 (122.1259, 54.1242) -> (122.1297, 54.0281)
  line L3347 (122.1297, 54.0281) -> (122.1297, 53.4781)
  line L3348 (122.1297, 53.4781) -> (122.1259, 53.382)
  line L3349 (122.1259, 53.382) -> (122.0958, 53.1921)
  line L3350 (122.0958, 53.1921) -> (122.0364, 53.0093)
  line L3351 (122.0364, 53.0093) -> (121.9492, 52.8381)
  line L3352 (121.9492, 52.8381) -> (121.8362, 52.6825)
  line L3353 (121.8362, 52.6825) -> (121.7003, 52.5466)
  line L3354 (121.7003, 52.5466) -> (121.5447, 52.4336)
  line L3355 (121.5447, 52.4336) -> (121.3735, 52.3464)
  line L3356 (121.3735, 52.3464) -> (121.1907, 52.287)
  line L3357 (121.1907, 52.287) -> (121.0008, 52.2569)
  line L3358 (121.0008, 52.2569) -> (120.8086, 52.2569)
  line L3359 (120.8086, 52.2569) -> (120.6187, 52.287)
  line L3360 (120.6187, 52.287) -> (120.4359, 52.3464)
  line L3361 (120.4359, 52.3464) -> (120.2646, 52.4336)
  line L3362 (120.2646, 52.4336) -> (120.1091, 52.5466)
  line L3363 (120.1091, 52.5466) -> (119.9732, 52.6825)
  line L3364 (119.9732, 52.6825) -> (119.8602, 52.8381)
  line L3365 (119.8602, 52.8381) -> (119.7729, 53.0093)
  line L3366 (119.7729, 53.0093) -> (119.7135, 53.1921)
  line L3367 (119.7135, 53.1921) -> (119.6835, 53.382)
  line L3368 (119.6835, 53.382) -> (119.6797, 53.4781)
  line L3369 (119.6797, 53.4781) -> (119.6797, 54.0281)
  line L3370 (119.6797, 54.0281) -> (119.6835, 54.1242)
  line L3371 (119.6835, 54.1242) -> (119.7135, 54.3141)
  line L3372 (119.7135, 54.3141) -> (119.7729, 54.4969)
  line L3373 (119.7729, 54.4969) -> (119.8602, 54.6682)
  line L3374 (119.8602, 54.6682) -> (119.9732, 54.8237)
  line L3375 (119.9732, 54.8237) -> (120.1091, 54.9596)
  line L3376 (120.1091, 54.9596) -> (120.2646, 55.0726)
  line L3377 (120.2646, 55.0726) -> (120.4359, 55.1599)
  line L3378 (120.4359, 55.1599) -> (120.6187, 55.2193)
  line L3379 (120.6187, 55.2193) -> (120.8086, 55.2493)
  line L3380 (120.8086, 55.2493) -> (121.0008, 55.2493)
  line L3381 (121.0008, 55.2493) -> (121.1907, 55.2193)
  line L3382 (16.536, 65.4179) -> (16.7297, 65.3872)
  line L3383 (16.7297, 65.3872) -> (16.9162, 65.3266)
  line L3384 (16.9162, 65.3266) -> (17.091, 65.2376)
  line L3385 (17.091, 65.2376) -> (17.2497, 65.1223)
  line L3386 (17.2497, 65.1223) -> (17.3884, 64.9836)
  line L3387 (17.3884, 64.9836) -> (17.5037, 64.8249)
  line L3388 (17.5037, 64.8249) -> (17.5927, 64.6501)
  line L3389 (17.5927, 64.6501) -> (17.6534, 64.4636)
  line L3390 (17.6534, 64.4636) -> (17.684, 64.2698)
  line L3391 (17.684, 64.2698) -> (17.684, 64.0737)
  line L3392 (17.684, 64.0737) -> (17.6534, 63.88)
  line L3393 (17.6534, 63.88) -> (17.5927, 63.6934)
  line L3394 (17.5927, 63.6934) -> (17.5037, 63.5186)
  line L3395 (17.5037, 63.5186) -> (17.3884, 63.36)
  line L3396 (17.3884, 63.36) -> (17.2497, 63.2213)
  line L3397 (17.2497, 63.2213) -> (17.091, 63.106)
  line L3398 (17.091, 63.106) -> (16.9162, 63.0169)
  line L3399 (16.9162, 63.0169) -> (16.7297, 62.9563)
  line L3400 (16.7297, 62.9563) -> (16.536, 62.9256)
  line L3401 (16.536, 62.9256) -> (16.4379, 62.9218)
  line L3402 (16.4379, 62.9218) -> (15.9379, 62.9218)
  line L3403 (15.9379, 62.9218) -> (15.8398, 62.9256)
  line L3404 (15.8398, 62.9256) -> (15.6461, 62.9563)
  line L3405 (15.6461, 62.9563) -> (15.4595, 63.0169)
  line L3406 (15.4595, 63.0169) -> (15.2848, 63.106)
  line L3407 (15.2848, 63.106) -> (15.1261, 63.2213)
  line L3408 (15.1261, 63.2213) -> (14.9874, 63.36)
  line L3409 (14.9874, 63.36) -> (14.8721, 63.5186)
  line L3410 (14.8721, 63.5186) -> (14.783, 63.6934)
  line L3411 (14.783, 63.6934) -> (14.7224, 63.88)
  line L3412 (14.7224, 63.88) -> (14.6917, 64.0737)
  line L3413 (14.6917, 64.0737) -> (14.6917, 64.2698)
  line L3414 (14.6917, 64.2698) -> (14.7224, 64.4636)
  line L3415 (14.7224, 64.4636) -> (14.783, 64.6501)
  line L3416 (14.783, 64.6501) -> (14.8721, 64.8249)
  line L3417 (14.8721, 64.8249) -> (14.9874, 64.9836)
  line L3418 (14.9874, 64.9836) -> (15.1261, 65.1223)
  line L3419 (15.1261, 65.1223) -> (15.2848, 65.2376)
  line L3420 (15.2848, 65.2376) -> (15.4595, 65.3266)
  line L3421 (15.4595, 65.3266) -> (15.6461, 65.3872)
  line L3422 (15.6461, 65.3872) -> (15.8398, 65.4179)
  line L3423 (15.8398, 65.4179) -> (15.9379, 65.4218)
  line L3424 (15.9379, 65.4218) -> (16.4379, 65.4218)
  line L3425 (16.4379, 65.4218) -> (16.536, 65.4179)
  line L3426 (24.156, 65.4179) -> (24.3497, 65.3872)
  line L3427 (24.3497, 65.3872) -> (24.5362, 65.3266)
  line L3428 (24.5362, 65.3266) -> (24.711, 65.2376)
  line L3429 (24.711, 65.2376) -> (24.8697, 65.1223)
  line L3430 (24.8697, 65.1223) -> (25.0084, 64.9836)
  line L3431 (25.0084, 64.9836) -> (25.1237, 64.8249)
  line L3432 (25.1237, 64.8249) -> (25.2127, 64.6501)
  line L3433 (25.2127, 64.6501) -> (25.2734, 64.4636)
  line L3434 (25.2734, 64.4636) -> (25.304, 64.2698)
  line L3435 (25.304, 64.2698) -> (25.304, 64.0737)
  line L3436 (25.304, 64.0737) -> (25.2734, 63.88)
  line L3437 (25.2734, 63.88) -> (25.2127, 63.6934)
  line L3438 (25.2127, 63.6934) -> (25.1237, 63.5186)
  line L3439 (25.1237, 63.5186) -> (25.0084, 63.36)
  line L3440 (25.0084, 63.36) -> (24.8697, 63.2213)
  line L3441 (24.8697, 63.2213) -> (24.711, 63.106)
  line L3442 (24.711, 63.106) -> (24.5362, 63.0169)
  line L3443 (24.5362, 63.0169) -> (24.3497, 62.9563)
  line L3444 (24.3497, 62.9563) -> (24.156, 62.9256)
  line L3445 (24.156, 62.9256) -> (24.0579, 62.9218)
  line L3446 (24.0579, 62.9218) -> (23.5579, 62.9218)
  line L3447 (23.5579, 62.9218) -> (23.4598, 62.9256)
  line L3448 (23.4598, 62.9256) -> (23.2661, 62.9563)
  line L3449 (23.2661, 62.9563) -> (23.0795, 63.0169)
  line L3450 (23.0795, 63.0169) -> (22.9048, 63.106)
  line L3451 (22.9048, 63.106) -> (22.7461, 63.2213)
  line L3452 (22.7461, 63.2213) -> (22.6074, 63.36)
  line L3453 (22.6074, 63.36) -> (22.4921, 63.5186)
  line L3454 (22.4921, 63.5186) -> (22.403, 63.6934)
  line L3455 (22.403, 63.6934) -> (22.3424, 63.88)
  line L3456 (22.3424, 63.88) -> (22.3117, 64.0737)
  line L3457 (22.3117, 64.0737) -> (22.3117, 64.2698)
  line L3458 (22.3117, 64.2698) -> (22.3424, 64.4636)
  line L3459 (22.3424, 64.4636) -> (22.403, 64.6501)
  line L3460 (22.403, 64.6501) -> (22.4921, 64.8249)
  line L3461 (22.4921, 64.8249) -> (22.6074, 64.9836)
  line L3462 (22.6074, 64.9836) -> (22.7461, 65.1223)
  line L3463 (22.7461, 65.1223) -> (22.9048, 65.2376)
  line L3464 (22.9048, 65.2376) -> (23.0795, 65.3266)
  line L3465 (23.0795, 65.3266) -> (23.2661, 65.3872)
  line L3466 (23.2661, 65.3872) -> (23.4598, 65.4179)
  line L3467 (23.4598, 65.4179) -> (23.5579, 65.4218)
  line L3468 (23.5579, 65.4218) -> (24.0579, 65.4218)
  line L3469 (24.0579, 65.4218) -> (24.156, 65.4179)
  line L3470 (51.461, 65.4179) -> (51.6547, 65.3872)
  line L3471 (51.6547, 65.3872) -> (51.8412, 65.3266)
  line L3472 (51.8412, 65.3266) -> (52.016, 65.2376)
  line L3473 (52.016, 65.2376) -> (52.1747, 65.1223)
  line L3474 (52.1747, 65.1223) -> (52.3134, 64.9836)
  line L3475 (52.3134, 64.9836) -> (52.4287, 64.8249)
  line L3476 (52.4287, 64.8249) -> (52.5177, 64.6501)
  line L3477 (52.5177, 64.6501) -> (52.5784, 64.4636)
  line L3478 (52.5784, 64.4636) -> (52.609, 64.2698)
  line L3479 (52.609, 64.2698) -> (52.609, 64.0737)
  line L3480 (52.609, 64.0737) -> (52.5783, 63.88)
  line L3481 (52.5783, 63.88) -> (52.5177, 63.6934)
  line L3482 (52.5177, 63.6934) -> (52.4287, 63.5186)
  line L3483 (52.4287, 63.5186) -> (52.3134, 63.36)
  line L3484 (52.3134, 63.36) -> (52.1747, 63.2213)
  line L3485 (52.1747, 63.2213) -> (52.016, 63.106)
  line L3486 (52.016, 63.106) -> (51.8412, 63.0169)
  line L3487 (51.8412, 63.0169) -> (51.6547, 62.9563)
  line L3488 (51.6547, 62.9563) -> (51.461, 62.9256)
  line L3489 (51.461, 62.9256) -> (51.3629, 62.9218)
  line L3490 (51.3629, 62.9218) -> (50.8629, 62.9218)
  line L3491 (50.8629, 62.9218) -> (50.7648, 62.9256)
  line L3492 (50.7648, 62.9256) -> (50.5711, 62.9563)
  line L3493 (50.5711, 62.9563) -> (50.3845, 63.0169)
  line L3494 (50.3845, 63.0169) -> (50.2098, 63.106)
  line L3495 (50.2098, 63.106) -> (50.0511, 63.2213)
  line L3496 (50.0511, 63.2213) -> (49.9124, 63.36)
  line L3497 (49.9124, 63.36) -> (49.7971, 63.5186)
  line L3498 (49.7971, 63.5186) -> (49.708, 63.6934)
  line L3499 (49.708, 63.6934) -> (49.6474, 63.88)
  line L3500 (49.6474, 63.88) -> (49.6167, 64.0737)
  line L3501 (49.6167, 64.0737) -> (49.6167, 64.2698)
  line L3502 (49.6167, 64.2698) -> (49.6474, 64.4636)
  line L3503 (49.6474, 64.4636) -> (49.708, 64.6501)
  line L3504 (49.708, 64.6501) -> (49.7971, 64.8249)
  line L3505 (49.7971, 64.8249) -> (49.9124, 64.9836)
  line L3506 (49.9124, 64.9836) -> (50.0511, 65.1223)
  line L3507 (50.0511, 65.1223) -> (50.2098, 65.2376)
  line L3508 (50.2098, 65.2376) -> (50.3845, 65.3266)
  line L3509 (50.3845, 65.3266) -> (50.5711, 65.3872)
  line L3510 (50.5711, 65.3872) -> (50.7648, 65.4179)
  line L3511 (50.7648, 65.4179) -> (50.8629, 65.4218)
  line L3512 (50.8629, 65.4218) -> (51.3629, 65.4218)
  line L3513 (51.3629, 65.4218) -> (51.461, 65.4179)
  line L3514 (59.081, 65.4179) -> (59.2747, 65.3872)
  line L3515 (59.2747, 65.3872) -> (59.4612, 65.3266)
  line L3516 (59.4612, 65.3266) -> (59.636, 65.2376)
  line L3517 (59.636, 65.2376) -> (59.7947, 65.1223)
  line L3518 (59.7947, 65.1223) -> (59.9334, 64.9836)
  line L3519 (59.9334, 64.9836) -> (60.0487, 64.8249)
  line L3520 (60.0487, 64.8249) -> (60.1377, 64.6501)
  line L3521 (60.1377, 64.6501) -> (60.1984, 64.4636)
  line L3522 (60.1984, 64.4636) -> (60.229, 64.2698)
  line L3523 (60.229, 64.2698) -> (60.229, 64.0737)
  line L3524 (60.229, 64.0737) -> (60.1983, 63.88)
  line L3525 (60.1983, 63.88) -> (60.1377, 63.6934)
  line L3526 (60.1377, 63.6934) -> (60.0487, 63.5186)
  line L3527 (60.0487, 63.5186) -> (59.9334, 63.36)
  line L3528 (59.9334, 63.36) -> (59.7947, 63.2213)
  line L3529 (59.7947, 63.2213) -> (59.636, 63.106)
  line L3530 (59.636, 63.106) -> (59.4612, 63.0169)
  line L3531 (59.4612, 63.0169) -> (59.2747, 62.9563)
  line L3532 (59.2747, 62.9563) -> (59.081, 62.9256)
  line L3533 (59.081, 62.9256) -> (58.9829, 62.9218)
  line L3534 (58.9829, 62.9218) -> (58.4829, 62.9218)
  line L3535 (58.4829, 62.9218) -> (58.3848, 62.9256)
  line L3536 (58.3848, 62.9256) -> (58.1911, 62.9563)
  line L3537 (58.1911, 62.9563) -> (58.0045, 63.0169)
  line L3538 (58.0045, 63.0169) -> (57.8298, 63.106)
  line L3539 (57.8298, 63.106) -> (57.6711, 63.2213)
  line L3540 (57.6711, 63.2213) -> (57.5324, 63.36)
  line L3541 (57.5324, 63.36) -> (57.4171, 63.5186)
  line L3542 (57.4171, 63.5186) -> (57.328, 63.6934)
  line L3543 (57.328, 63.6934) -> (57.2674, 63.88)
  line L3544 (57.2674, 63.88) -> (57.2367, 64.0737)
  line L3545 (57.2367, 64.0737) -> (57.2367, 64.2698)
  line L3546 (57.2367, 64.2698) -> (57.2674, 64.4636)
  line L3547 (57.2674, 64.4636) -> (57.328, 64.6501)
  line L3548 (57.328, 64.6501) -> (57.4171, 64.8249)
  line L3549 (57.4171, 64.8249) -> (57.5324, 64.9836)
  line L3550 (57.5324, 64.9836) -> (57.6711, 65.1223)
  line L3551 (57.6711, 65.1223) -> (57.8298, 65.2376)
  line L3552 (57.8298, 65.2376) -> (58.0045, 65.3266)
  line L3553 (58.0045, 65.3266) -> (58.1911, 65.3872)
  line L3554 (58.1911, 65.3872) -> (58.3848, 65.4179)
  line L3555 (58.3848, 65.4179) -> (58.4829, 65.4218)
  line L3556 (58.4829, 65.4218) -> (58.9829, 65.4218)
  line L3557 (58.9829, 65.4218) -> (59.081, 65.4179)
  line L3558 (86.386, 65.4179) -> (86.5797, 65.3872)
  line L3559 (86.5797, 65.3872) -> (86.7662, 65.3266)
  line L3560 (86.7662, 65.3266) -> (86.941, 65.2376)
  line L3561 (86.941, 65.2376) -> (87.0997, 65.1223)
  line L3562 (87.0997, 65.1223) -> (87.2384, 64.9836)
  line L3563 (87.2384, 64.9836) -> (87.3537, 64.8249)
  line L3564 (87.3537, 64.8249) -> (87.4427, 64.6501)
  line L3565 (87.4427, 64.6501) -> (87.5034, 64.4636)
  line L3566 (87.5034, 64.4636) -> (87.534, 64.2698)
  line L3567 (87.534, 64.2698) -> (87.534, 64.0737)
  line L3568 (87.534, 64.0737) -> (87.5034, 63.88)
  line L3569 (87.5033, 63.88) -> (87.4427, 63.6934)
  line L3570 (87.4427, 63.6934) -> (87.3537, 63.5186)
  line L3571 (87.3537, 63.5186) -> (87.2384, 63.36)
  line L3572 (87.2384, 63.36) -> (87.0997, 63.2213)
  line L3573 (87.0997, 63.2213) -> (86.941, 63.106)
  line L3574 (86.941, 63.106) -> (86.7662, 63.0169)
  line L3575 (86.7662, 63.0169) -> (86.5797, 62.9563)
  line L3576 (86.5797, 62.9563) -> (86.386, 62.9256)
  line L3577 (86.386, 62.9256) -> (86.2879, 62.9218)
  line L3578 (86.2879, 62.9218) -> (85.7879, 62.9218)
  line L3579 (85.7879, 62.9218) -> (85.6898, 62.9256)
  line L3580 (85.6898, 62.9256) -> (85.4961, 62.9563)
  line L3581 (85.4961, 62.9563) -> (85.3095, 63.0169)
  line L3582 (85.3095, 63.0169) -> (85.1348, 63.106)
  line L3583 (85.1348, 63.106) -> (84.9761, 63.2213)
  line L3584 (84.9761, 63.2213) -> (84.8374, 63.36)
  line L3585 (84.8374, 63.36) -> (84.7221, 63.5186)
  line L3586 (84.7221, 63.5186) -> (84.633, 63.6934)
  line L3587 (84.633, 63.6934) -> (84.5724, 63.88)
  line L3588 (84.5724, 63.88) -> (84.5417, 64.0737)
  line L3589 (84.5417, 64.0737) -> (84.5417, 64.2698)
  line L3590 (84.5417, 64.2698) -> (84.5724, 64.4636)
  line L3591 (84.5724, 64.4636) -> (84.633, 64.6501)
  line L3592 (84.633, 64.6501) -> (84.7221, 64.8249)
  line L3593 (84.7221, 64.8249) -> (84.8374, 64.9836)
  line L3594 (84.8374, 64.9836) -> (84.9761, 65.1223)
  line L3595 (84.9761, 65.1223) -> (85.1348, 65.2376)
  line L3596 (85.1348, 65.2376) -> (85.3095, 65.3266)
  line L3597 (85.3095, 65.3266) -> (85.4961, 65.3872)
  line L3598 (85.4961, 65.3872) -> (85.6898, 65.4179)
  line L3599 (85.6898, 65.4179) -> (85.7879, 65.4218)
  line L3600 (85.7879, 65.4218) -> (86.2879, 65.4218)
  line L3601 (86.2879, 65.4218) -> (86.386, 65.4179)
  line L3602 (94.006, 65.4179) -> (94.1997, 65.3872)
  line L3603 (94.1997, 65.3872) -> (94.3862, 65.3266)
  line L3604 (94.3862, 65.3266) -> (94.561, 65.2376)
  line L3605 (94.561, 65.2376) -> (94.7197, 65.1223)
  line L3606 (94.7197, 65.1223) -> (94.8584, 64.9836)
  line L3607 (94.8584, 64.9836) -> (94.9737, 64.8249)
  line L3608 (94.9737, 64.8249) -> (95.0627, 64.6501)
  line L3609 (95.0627, 64.6501) -> (95.1233, 64.4636)
  line L3610 (95.1233, 64.4636) -> (95.154, 64.2698)
  line L3611 (95.154, 64.2698) -> (95.154, 64.0737)
  line L3612 (95.154, 64.0737) -> (95.1233, 63.88)
  line L3613 (95.1233, 63.88) -> (95.0627, 63.6934)
  line L3614 (95.0627, 63.6934) -> (94.9737, 63.5186)
  line L3615 (94.9737, 63.5186) -> (94.8584, 63.36)
  line L3616 (94.8584, 63.36) -> (94.7197, 63.2213)
  line L3617 (94.7197, 63.2213) -> (94.561, 63.106)
  line L3618 (94.561, 63.106) -> (94.3862, 63.0169)
  line L3619 (94.3862, 63.0169) -> (94.1997, 62.9563)
  line L3620 (94.1997, 62.9563) -> (94.006, 62.9256)
  line L3621 (94.006, 62.9256) -> (93.9079, 62.9218)
  line L3622 (93.9079, 62.9218) -> (93.4079, 62.9218)
  line L3623 (93.4079, 62.9218) -> (93.3098, 62.9256)
  line L3624 (93.3098, 62.9256) -> (93.1161, 62.9563)
  line L3625 (93.1161, 62.9563) -> (92.9295, 63.0169)
  line L3626 (92.9295, 63.0169) -> (92.7548, 63.106)
  line L3627 (92.7548, 63.106) -> (92.5961, 63.2213)
  line L3628 (92.5961, 63.2213) -> (92.4574, 63.36)
  line L3629 (92.4574, 63.36) -> (92.3421, 63.5186)
  line L3630 (92.3421, 63.5186) -> (92.253, 63.6934)
  line L3631 (92.253, 63.6934) -> (92.1924, 63.88)
  line L3632 (92.1924, 63.88) -> (92.1617, 64.0737)
  line L3633 (92.1617, 64.0737) -> (92.1617, 64.2698)
  line L3634 (92.1617, 64.2698) -> (92.1924, 64.4636)
  line L3635 (92.1924, 64.4636) -> (92.253, 64.6501)
  line L3636 (92.253, 64.6501) -> (92.3421, 64.8249)
  line L3637 (92.3421, 64.8249) -> (92.4574, 64.9836)
  line L3638 (92.4574, 64.9836) -> (92.5961, 65.1223)
  line L3639 (92.5961, 65.1223) -> (92.7548, 65.2376)
  line L3640 (92.7548, 65.2376) -> (92.9295, 65.3266)
  line L3641 (92.9295, 65.3266) -> (93.1161, 65.3872)
  line L3642 (93.1161, 65.3872) -> (93.3098, 65.4179)
  line L3643 (93.3098, 65.4179) -> (93.4079, 65.4218)
  line L3644 (93.4079, 65.4218) -> (93.9079, 65.4218)
  line L3645 (93.9079, 65.4218) -> (94.006, 65.4179)
  line L3646 (121.311, 65.4179) -> (121.5047, 65.3872)
  line L3647 (121.5047, 65.3872) -> (121.6912, 65.3266)
  line L3648 (121.6912, 65.3266) -> (121.866, 65.2376)
  line L3649 (121.866, 65.2376) -> (122.0247, 65.1223)
  line L3650 (122.0247, 65.1223) -> (122.1634, 64.9836)
  line L3651 (122.1634, 64.9836) -> (122.2787, 64.8249)
  line L3652 (122.2787, 64.8249) -> (122.3677, 64.6501)
  line L3653 (122.3677, 64.6501) -> (122.4283, 64.4636)
  line L3654 (122.4283, 64.4636) -> (122.459, 64.2698)
  line L3655 (122.459, 64.2698) -> (122.459, 64.0737)
  line L3656 (122.459, 64.0737) -> (122.4283, 63.88)
  line L3657 (122.4283, 63.88) -> (122.3677, 63.6934)
  line L3658 (122.3677, 63.6934) -> (122.2787, 63.5186)
  line L3659 (122.2787, 63.5186) -> (122.1634, 63.36)
  line L3660 (122.1634, 63.36) -> (122.0247, 63.2213)
  line L3661 (122.0247, 63.2213) -> (121.866, 63.106)
  line L3662 (121.866, 63.106) -> (121.6912, 63.0169)
  line L3663 (121.6912, 63.0169) -> (121.5047, 62.9563)
  line L3664 (121.5047, 62.9563) -> (121.311, 62.9256)
  line L3665 (121.311, 62.9256) -> (121.2129, 62.9218)
  line L3666 (121.2129, 62.9218) -> (120.7129, 62.9218)
  line L3667 (120.7129, 62.9218) -> (120.6148, 62.9256)
  line L3668 (120.6148, 62.9256) -> (120.4211, 62.9563)
  line L3669 (120.4211, 62.9563) -> (120.2345, 63.0169)
  line L3670 (120.2345, 63.0169) -> (120.0598, 63.106)
  line L3671 (120.0598, 63.106) -> (119.9011, 63.2213)
  line L3672 (119.9011, 63.2213) -> (119.7624, 63.36)
  line L3673 (119.7624, 63.36) -> (119.6471, 63.5186)
  line L3674 (119.6471, 63.5186) -> (119.558, 63.6934)
  line L3675 (119.558, 63.6934) -> (119.4974, 63.88)
  line L3676 (119.4974, 63.88) -> (119.4667, 64.0737)
  line L3677 (119.4667, 64.0737) -> (119.4667, 64.2698)
  line L3678 (119.4667, 64.2698) -> (119.4974, 64.4636)
  line L3679 (119.4974, 64.4636) -> (119.558, 64.6501)
  line L3680 (119.558, 64.6501) -> (119.6471, 64.8249)
  line L3681 (119.6471, 64.8249) -> (119.7624, 64.9836)
  line L3682 (119.7624, 64.9836) -> (119.9011, 65.1223)
  line L3683 (119.9011, 65.1223) -> (120.0598, 65.2376)
  line L3684 (120.0598, 65.2376) -> (120.2345, 65.3266)
  line L3685 (120.2345, 65.3266) -> (120.4211, 65.3872)
  line L3686 (120.4211, 65.3872) -> (120.6148, 65.4179)
  line L3687 (120.6148, 65.4179) -> (120.7129, 65.4218)
  line L3688 (120.7129, 65.4218) -> (121.2129, 65.4218)
  line L3689 (121.2129, 65.4218) -> (121.311, 65.4179)
  line L3690 (128.931, 65.4179) -> (129.1247, 65.3872)
  line L3691 (129.1247, 65.3872) -> (129.3112, 65.3266)
  line L3692 (129.3112, 65.3266) -> (129.486, 65.2376)
  line L3693 (129.486, 65.2376) -> (129.6447, 65.1223)
  line L3694 (129.6447, 65.1223) -> (129.7834, 64.9836)
  line L3695 (129.7834, 64.9836) -> (129.8987, 64.8249)
  line L3696 (129.8987, 64.8249) -> (129.9877, 64.6501)
  line L3697 (129.9877, 64.6501) -> (130.0483, 64.4636)
  line L3698 (130.0483, 64.4636) -> (130.079, 64.2698)
  line L3699 (130.079, 64.2698) -> (130.079, 64.0737)
  line L3700 (130.079, 64.0737) -> (130.0483, 63.88)
  line L3701 (130.0483, 63.88) -> (129.9877, 63.6934)
  line L3702 (129.9877, 63.6934) -> (129.8987, 63.5186)
  line L3703 (129.8987, 63.5186) -> (129.7834, 63.36)
  line L3704 (129.7834, 63.36) -> (129.6447, 63.2213)
  line L3705 (129.6447, 63.2213) -> (129.486, 63.106)
  line L3706 (129.486, 63.106) -> (129.3112, 63.0169)
  line L3707 (129.3112, 63.0169) -> (129.1247, 62.9563)
  line L3708 (129.1247, 62.9563) -> (128.931, 62.9256)
  line L3709 (128.931, 62.9256) -> (128.8329, 62.9218)
  line L3710 (128.8329, 62.9218) -> (128.3329, 62.9218)
  line L3711 (128.3329, 62.9218) -> (128.2348, 62.9256)